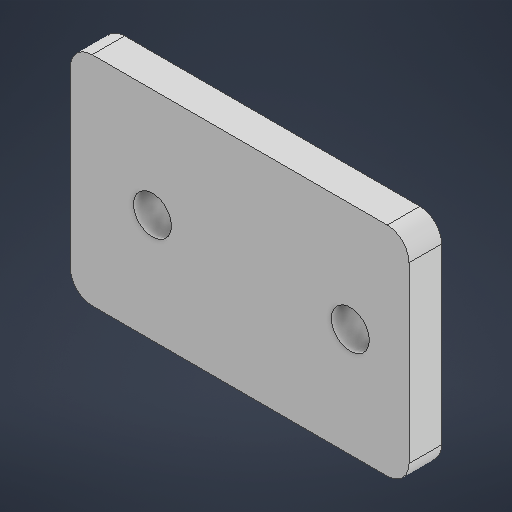
# Autodesk Inventor part: DC Motor Bracket Spacer
Saved by Autodesk Inventor 2027.1 (Build 311270010, 270A)
## iProperties
Created: 2026-11-02
Part Number: DC Motor Bracket Spacer
Material: Generic
Document SubType Name: Modeling
Designer: Ahmed
Density: 1 g/cm^3
Appearance: Default
Author: Ahmed
Autodesk Inventor part; units mm, degrees
ref_plane "YZ Plane" through (0, 0, 0) normal (1, 0, 0) x (0, 1, 0)
ref_plane "XZ Plane" through (0, 0, 0) normal (0, 1, 0) x (-1, 0, 0)
ref_plane "XY Plane" through (0, 0, 0) normal (0, 0, 1) x (1, 0, 0)
sketch "Sketch1" plane through (0, 0, 0) normal (0, 0, 1) x (1, 0, 0)
  line L0 (0, 0) -> (31.15, 0)
  line L1 (31.15, 0) -> (31.15, 27)
  line L2 (31.15, 27) -> (0, 27)
  line L3 (0, 27) -> (0, 0)
  arc A0 (31.15, 25) -> (29.15, 27) centre (29.15, 25) ccw
  arc A1 (29.15, 0) -> (31.15, 2) centre (29.15, 2) ccw
  line L4 (0, 13.5) -> (31.15, 13.5)
  circle A2 centre (7.55, 13.5) radius 1.75
  circle A3 centre (25.75, 13.5) radius 1.75
  point P0 (16.65, 13.5)
  dimension "d0" = 31.15
  dimension "d1" = 27
  dimension "d4" = 2
  dimension "d5" = 16.65
  dimension "d6" = 3.5
  dimension "d7" = 3.5
  dimension "d8" = 9.1
  dimension "d9" = 9.1
  constraints: 10 end point, 7 point on line, 4 centre point, 4 point on circle, 4 tangent, 3 parallel, 2 midpoint, 1 equal radius, 1 horizontal, 1 perpendicular
  measures "d0" distance of L1.end L2.end
  measures "d1" distance of L1.end L0.end
  measures "d4" radius of A0
  measures "d5" distance from line of L3 point (16.65, 13.5)
  measures "d6" diameter of A2
  measures "d7" diameter of A3
  measures "d8" distance of point (16.65, 13.5) A2.centre
  measures "d9" distance of point (16.65, 13.5) A3.centre
extrude "Extrusion1" add sketch "Sketch1" along normal blind 3 contours L3 L4 A2 A3 L1 A1 L0 | A1 L1 L0 | L3 L2 A0 L1 L4 A3 A2 | L2 L1 A0
thicken "Thicken3" operation cut thickness 3.5 both sides no extend neighbours no toward (0, 1, 0) faces at (10.3833, 0, 1)
thicken "Thicken4" operation cut thickness 3.5 both sides no extend neighbours no toward (0, -1, 0) faces at (20.7667, 27, 1)
fillet "Fillet1" radius 2 4 edges at (31.15, 3.5, 1.5) (31.15, 23.5, 1.5) (0, 23.5, 1.5) (0, 3.5, 1.5)
body "Solid1"
